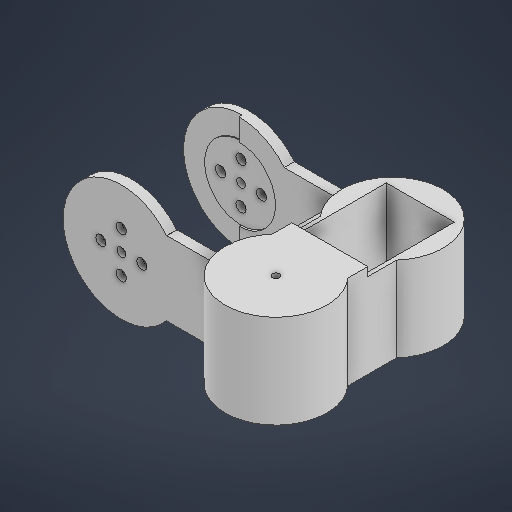
# Autodesk Inventor part: SuporteGarraP2
Saved by Autodesk Inventor 2027.1 (Build 311270010, 270A)
## iProperties
Created: 2026-10-08
Part Number: SuporteGarraP2
Material: Generic
Document SubType Name: Modeling
Designer: jose2
Density: 1 g/cm^3
Appearance: Default
Author: jose2
Autodesk Inventor part; units mm, degrees
ref_plane "YZ Plane" through (0, 0, 0) normal (1, 0, 0) x (0, 1, 0)
sketch "Sketch1" plane through (0, 0, 0) normal (0, 0, 1) x (1, 0, 0)
  circle A0 centre (0, 0) radius 7
  circle A1 centre (0, 0) radius 1.5
  circle A2 centre (0, 7) radius 1.75
  circle A3 centre (0, 0) radius 20
  circle A4 centre (-7, 0) radius 1.75
  circle A5 centre (0, -7) radius 1.75
  circle A6 centre (7, 0) radius 1.75
  dimension "d0" = 14
  dimension "d1" = 3
  dimension "d2" = 3.5
  dimension "d3" = 40
  dimension "d6" = 360
  constraints: 6 centre point, 3 coincident, 1 vertical alignment, 11 other
  measures "d1" diameter of A1
  measures "d2" diameter of A2
  measures "d3" diameter of A3
extrude "Extrusion1" add sketch "Sketch1" along normal blind 5 contours A6 A0 A5 A4 A2 | A3
sketch "Sketch2" plane through (0, 0, 5) normal (0, 0, 1) x (1, 0, 0)
  circle A0 centre (0, 0) radius 1.5 projected
  line L0 (-35, 12.6589) -> (35, -12.6589) construction
  line L1 (35, 12.6589) -> (-35, -12.6589) construction
  line L2 (35, 12.6589) -> (0, 12.6589)
  line L3 (0, 12.6589) -> (0, -12.6589)
  line L4 (0, -12.6589) -> (35, -12.6589)
  line L5 (35, -12.6589) -> (35, 12.6589)
  circle A1 centre (7, 0) radius 1.75 projected
  circle A2 centre (7, 0) radius 1.15
  circle A3 centre (0, 0) radius 20
  point P0 (15.484, 12.6589)
  point P1 (15.484, -12.6589)
  dimension "d10" = 70
  constraints: 12 end point, 2 centre point, 2 coincident, 2 midpoint, 2 parallel, 1 horizontal, 1 perpendicular
  measures "d10" distance of L0.end L1.end
extrude "Extrusion2" add sketch "Sketch2" against normal blind 5 contours L2 L5 L4 A3
sketch "Sketch3" plane through (35, -12.6589, 5) normal (1, 0, 0) x (0, 0, -1)
  line L0 (5, 25.3178) -> (5, 0) projected
  line L1 (5, 0) -> (-14.4, 0)
  line L2 (-14.4, 0) -> (-14.4, 25.3178)
  line L3 (-14.4, 25.3178) -> (5, 25.3178)
  line L4 (5, 25.3178) -> (5, 0)
  point P0 (5, 12.6589)
  dimension "d13" = 19.4
  constraints: 8 end point, 2 parallel, 1 horizontal, 1 perpendicular
  measures "d13" distance of L2.end L3.end
extrude "Extrusion3" add sketch "Sketch3" along normal blind 3
ref_plane "Work Plane2" through (15.484, 0, 5) normal (0, 1, 0) x (1, 0, 0)
sketch "Sketch7" plane through (15.484, 0, 5) normal (0, 1, 0) x (1, 0, 0)
  line L0 (23.866, 12.628) -> (47.166, 12.628)
  line L1 (47.166, 12.628) -> (47.166, -31.372)
  line L2 (47.166, -31.372) -> (23.866, -31.372)
  line L3 (23.866, -31.372) -> (23.866, 12.628)
  line L4 (23.866, 12.628) -> (47.166, -31.372) construction
  line L5 (47.166, 12.628) -> (23.866, -31.372) construction
  line L6 (22.516, 14.628) -> (48.516, 14.628)
  line L7 (48.516, 14.628) -> (48.516, -33.372)
  line L8 (48.516, -33.372) -> (22.516, -33.372)
  line L9 (22.516, -33.372) -> (22.516, 14.628)
  line L10 (22.516, 14.628) -> (48.516, -33.372) construction
  line L11 (48.516, 14.628) -> (22.516, -33.372) construction
  circle A0 centre (35.516, 3.028) radius 17.428
  line L12 (22.516, -10.5757) -> (22.516, -33.372)
  line L13 (48.516, -10.5757) -> (48.516, -33.372)
  line L14 (19.516, -14.4) -> (22.516, -14.4) projected
  line L15 (22.516, 5) -> (22.516, -14.4) projected
  line L16 (48.516, -33.372) -> (22.516, -33.372)
  line L17 (22.516, -33.372) -> (22.516, -14.4)
  line L18 (22.516, -14.4) -> (48.516, -14.4)
  line L19 (48.516, -14.4) -> (48.516, -33.372)
  line L20 (0, 5) -> (22.516, 5) projected
  point P0 (-15.484, 5)
  point P1 (35.516, -9.372)
  point P2 (35.516, -9.372)
  point P3 (35.516, 12.628)
  point P4 (35.516, -14.4)
  point P5 (21.016, -14.4)
  point P6 (22.516, -9.372)
  point P7 (48.516, -8.5795)
  point P8 (22.516, -8.5795)
  dimension "d37" = 34.856
  dimension "d33" = 23.3
  dimension "d34" = 44
  dimension "d35" = 26
  dimension "d36" = 48
  dimension "d38" = 9.6
  dimension "d39" = 11.65
  dimension "d42" = 0
  dimension "d43" = 27.028
  dimension "d44" = 0
  dimension "d57" = 1.972
  constraints: 36 end point, 8 midpoint, 6 parallel, 3 perpendicular, 1 horizontal, 3 other
  measures "d33" distance of L1.end L3.start
  measures "d34" distance of L1.start L1.end
  measures "d35" distance of L7.end L9.start
  measures "d36" distance of L7.start L7.end
  measures "d38" distance of point (35.516, 12.628) point (35.516, 3.028)
  measures "d39" distance from line of L3 point (35.516, 3.028)
  measures "d42" vertical distance of point (21.016, -14.4) point (35.516, -14.4)
  measures "d43" distance of point (35.516, 12.628) point (35.516, -14.4)
  measures "d44" distance from line of point (22.516, -9.372) L15
  measures "d57" distance from line of L20 point (35.516, 3.028)
extrude "Extrusion8" add sketch "Sketch7" along normal mid plane 29 contours L3 A0 L9 L6 L7 L1 L0 | L3 L18 L9 A0 | A0 L7 L18 L1 | L3 L2 L1 L18 L7 L8 L9 | A0 L20 L9 | L7 L6 L9 L20 A0
sketch "Sketch8" plane through (35, -12.6589, 19.4) normal (0, 0, 1) x (1, 0, 0)
  line L0 (0, 25.3178) -> (0, 0) projected
  line L1 (3, 0) -> (3, -1.8411) projected
  line L2 (0, 25.3178) -> (3, 25.3178)
  line L3 (3, 25.3178) -> (3, 0)
  line L4 (3, 0) -> (0, 0)
  line L5 (0, 0) -> (0, 25.3178)
  point P0 (-35, 12.6589)
  constraints: 8 end point, 2 parallel, 1 horizontal, 1 perpendicular
extrude "Extrusion9" add sketch "Sketch8" along normal blind 19.4
sketch "Sketch9" plane through (35, -12.6589, 38.8) normal (0, 0, 1) x (1, 0, 0)
  circle A0 centre (-35, 12.6589) radius 1.5 projected
  circle A1 centre (-35, 12.6589) radius 19.9497
  circle A2 centre (-35, 12.6589) radius 2
  circle A3 centre (-35, 5.6589) radius 1.15
  circle A4 centre (-28, 12.6589) radius 1.15
  circle A5 centre (-35, 19.6589) radius 1.15
  circle A6 centre (-42, 12.6589) radius 1.15
  line L0 (-19.516, 25.3178) -> (-1.3161, 25.3178) projected
  line L1 (-1.3161, 25.3178) -> (-19.516, 25.3178)
  line L2 (-1.3161, 25.3178) -> (-1.428, 0.022)
  line L3 (-1.428, -1.8411) -> (-1.428, 27.1589) projected
  line L4 (-19.4979, 0.102) -> (-1.428, 0.022)
  line L5 (-1.1629, 0) -> (-1.1629, 25.3178) projected
  line L6 (-1.1629, 25.3178) -> (-19.4979, 25.3178)
  line L7 (-19.4979, 25.3178) -> (-19.4979, 0.102)
  line L8 (-19.4979, 0.102) -> (-1.1629, 0.102)
  line L9 (-1.1629, 0.102) -> (-1.1629, 25.3178)
  line L10 (-19.516, 0) -> (-1.3161, 0) projected
  line L11 (-1.3161, 0) -> (-19.4979, 0)
  line L12 (-19.4979, 0) -> (-19.4979, 25.3178)
  line L13 (-19.4979, 25.3178) -> (-1.3161, 25.3178)
  line L14 (-1.3161, 25.3178) -> (-1.3161, 0)
  line L15 (3, 0) -> (3, 25.3178) projected
  line L16 (-1.3161, 25.3178) -> (3, 25.3178)
  line L17 (3, 25.3178) -> (3, 0)
  line L18 (3, 0) -> (-1.3161, 0)
  line L19 (-1.3161, 0) -> (-1.3161, 25.3178)
  circle A7 centre (-28, 12.6589) radius 1.75
  circle A8 centre (-35, 19.6589) radius 1.75
  circle A9 centre (-42, 12.6589) radius 1.75
  circle A10 centre (-35, 5.6589) radius 1.75
  point P0 (-1.428, 0.102)
  point P1 (-1.428, 25.3178)
  point P2 (-19.4979, 25.2158)
  point P3 (-19.4979, 0.102)
  dimension "d49" = 4
  dimension "d86" = 3.5
  dimension "d89" = 360
  constraints: 30 end point, 9 centre point, 7 coincident, 7 equal length, 4 perpendicular, 3 horizontal, 1 point on line, 12 other
  measures "d49" diameter of A2
  measures "d86" diameter of A7
extrude "Extrusion10" add sketch "Sketch9" along normal blind 5 contours L7 A1 | L8 L2 L4 | A1 L7 | A1 L7 L0 L3 L8 | L4 L3 L10 L12 | L2 L8 L14 L10 L3 | L3 L0 L2 | L2 L14 L8 | L6 L5 L8 L14 | L8 L5 L18 L14 | L16 L15 L18 L5 | A2 | A3 | A4 | A5 | A6 | A7 | A8 | A9 | A10
sketch "Sketch11" plane through (15.484, 14.5, 5) normal (0, 1, 0) x (1, 0, 0)
  line L0 (48.516, -33.372) -> (48.516, -8.5795) projected
  line L1 (22.516, -8.5795) -> (22.516, -33.372) projected
  line L2 (48.516, -33.372) -> (22.516, -33.372)
  line L3 (22.516, -33.372) -> (22.516, -18.372)
  line L4 (22.516, -18.372) -> (48.516, -18.372)
  line L5 (48.516, -18.372) -> (48.516, -33.372)
  point P0 (-15.484, 5)
  point P1 (48.516, -18.372)
  dimension "d52" = 15
  constraints: 8 end point, 2 parallel, 1 horizontal, 1 perpendicular, 1 point on line
  measures "d52" distance of L2.end L3.end
extrude "Extrusion11" add sketch "Sketch11" along normal blind 3
sketch "Sketch12" plane through (15.484, -14.5, 5) normal (0, -1, 0) x (1, 0, 0)
  line L0 (48.516, 33.372) -> (48.516, 18.372) projected
  line L1 (48.516, 18.372) -> (22.516, 18.372) projected
  line L2 (48.516, 33.372) -> (22.516, 33.372)
  line L3 (22.516, 33.372) -> (22.516, 18.372)
  line L4 (22.516, 18.372) -> (48.516, 18.372)
  line L5 (48.516, 18.372) -> (48.516, 33.372)
  point P0 (-15.484, -5)
  constraints: 8 end point, 2 parallel, 1 horizontal, 1 perpendicular
extrude "Extrusion12" add sketch "Sketch12" along normal blind 3
sketch "Sketch13" plane through (15.484, 17.5, 5) normal (0, 1, 0) x (1, 0, 0)
  circle A0 centre (35.516, -36.828) radius 17.428
  line L0 (22.516, -38.8) -> (0.0182, -38.8) projected
  line L1 (22.516, -33.372) -> (22.516, -38.8) projected
  line L2 (48.516, -33.372) -> (48.516, -18.372) projected
  line L3 (48.516, -33.372) -> (48.516, -25.2205)
  line L4 (48.516, -33.372) -> (22.516, -33.372)
  line L5 (22.516, -33.372) -> (22.516, -38.8)
  line L6 (22.516, -38.8) -> (18.2, -38.8)
  line L7 (22.516, -8.5795) -> (22.516, -33.372) projected
  line L8 (22.516, -33.372) -> (22.516, -25.2205)
  point P0 (-15.484, 5)
  point P1 (22.516, -36.086)
  dimension "d58" = 34.856
  dimension "d59" = 1.972
  dimension "d60" = 13
  constraints: 10 end point, 3 point on circle, 3 point on line, 2 perpendicular, 1 centre point, 1 midpoint
  measures "d58" diameter of A0
  measures "d59" distance from line of L0 A0.centre
  measures "d60" horizontal distance of point (22.516, -36.086) A0.centre
extrude "Extrusion13" add sketch "Sketch13" against normal blind 35 contours A0 L0 L1 L4 L2 | A0 L7 L1 L0
sketch "Sketch14" plane through (15.484, 17.5, 5) normal (0, 1, 0) x (1, 0, 0)
  arc A0 (22.516, -25.2205) -> (48.516, -25.2205) centre (35.516, -36.828) ccw projected
  circle A1 centre (35.516, -36.828) radius 10.1326
  circle A2 centre (35.516, -36.828) radius 1.25
  point P0 (-15.484, 5)
  dimension "d63" = 2.5
  constraints: 2 centre point, 2 coincident
  measures "d63" diameter of A2
extrude "Extrusion14" cut sketch "Sketch14" against normal up to surface (35 mm away) contours A2
ref_plane "Work Plane3" through (0, 0, 21.9) normal (0, 0, 1) x (1, 0, 0)
sketch "Sketch17" plane through (0, 0, 21.9) normal (0, 0, 1) x (1, 0, 0)
  line L0 (-26.6538, -23.934) -> (33.8507, -23.934)
  line L1 (33.8507, -23.934) -> (33.8507, 28.6204)
  line L2 (33.8507, 28.6204) -> (-26.6538, 28.6204)
  line L3 (-26.6538, 28.6204) -> (-26.6538, -23.934)
  point P0 (0, 0)
  constraints: 8 end point, 2 parallel, 1 horizontal, 1 perpendicular
extrude "Extrusion17" cut sketch "Sketch17" along normal mid plane 36.8125
extrude "Extrusion18" cut sketch "Sketch9" along normal blind 10 contours A3 | A4 | A5 | A6 | A7 | A8 | A9 | A10
sketch "Sketch18" plane through (15.484, -17.5, 5) normal (0, -1, 0) x (1, 0, 0)
  circle A0 centre (35.516, 36.828) radius 1.25 projected
  circle A1 centre (35.516, 36.828) radius 24.1619
  point P0 (-15.484, -5)
  constraints: 1 centre point, 1 coincident
extrude "Extrusion19" cut sketch "Sketch18" against normal blind 3
sketch "Sketch19" plane through (0, 0, 40.3063) normal (0, 0, -1) x (-1, 0, 0)
  circle A0 centre (0, 0) radius 1.5 projected
  circle A1 centre (0, 0) radius 12.5
  dimension "d95" = 25
  constraints: 1 centre point, 1 coincident
  measures "d95" diameter of A1
extrude "Extrusion20" cut sketch "Sketch19" along normal blind 37.5 and the other way blind 1.5
sketch "Sketch20" plane through (0, 0, 3.4938) normal (0, 0, 1) x (1, 0, 0)
  circle A0 centre (0, 0) radius 1.5 projected
  circle A1 centre (0, 0) radius 12.5
  circle A2 centre (0, 0) radius 20
  circle A3 centre (0, 0) radius 12.5 projected
  line L0 (0, 12.5) -> (0, 20)
  line L1 (0, -20) -> (0, -12.5)
  constraints: 4 end point, 4 point on circle, 2 centre point, 2 coincident, 1 point on line, 1 vertical
extrude "Extrusion21" cut sketch "Sketch20" against normal blind 1 contours A1 L1 A2 L0 picked at (-2.5926, -17.1852)
body "Solid1"
